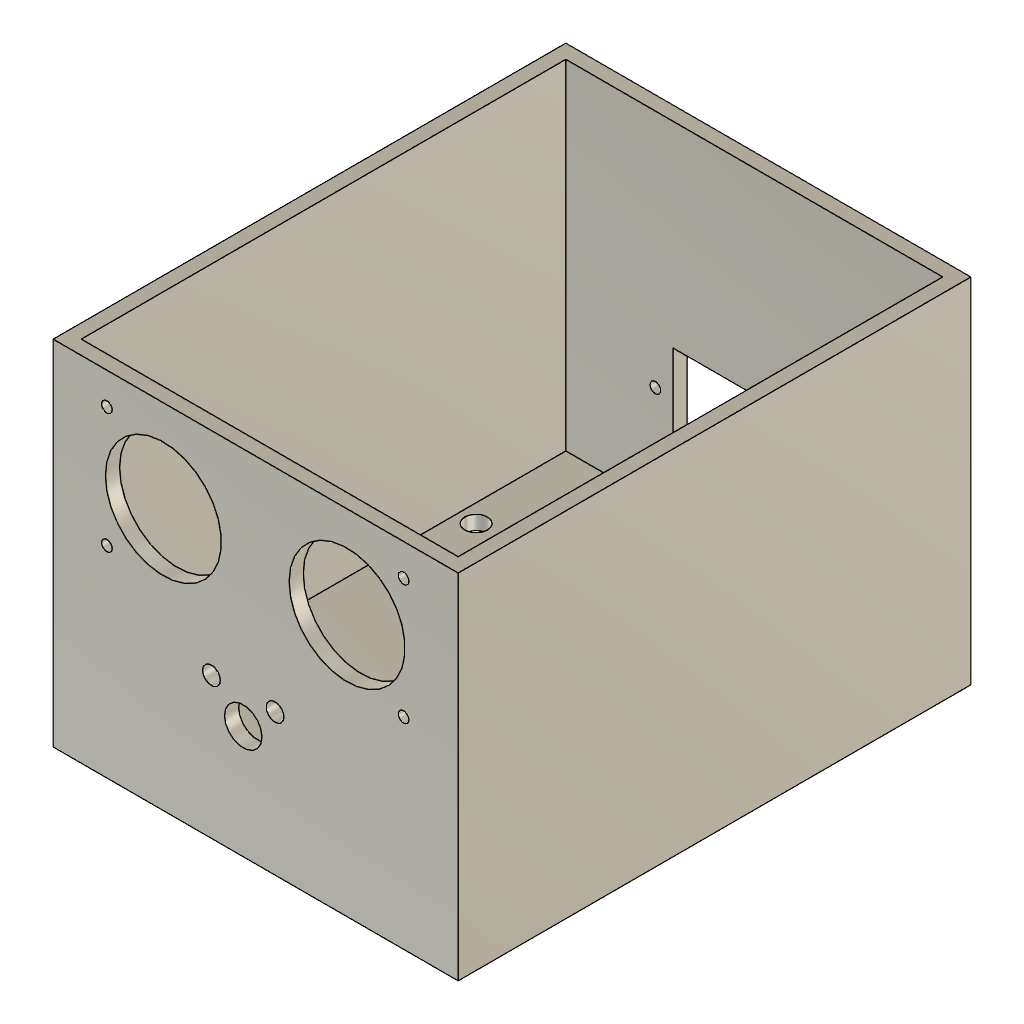
StatusDial_caseV1 (Autodesk Fusion 360 design; units mm, degrees)
part number: 2026-11-27-08-45-43-550
Autodesk Fusion 360 part; units mm, degrees
sketch "Sketch1" plane through (0, 0, 0) normal (0, 0, 1) x (1, 0, 0)
  line L0 (0, 0) -> (53.34, 0)
  line L1 (53.34, 0) -> (53.34, -68.58)
  line L2 (53.34, -68.58) -> (0, -68.58)
  line L3 (0, -68.58) -> (0, 0)
  circle A0 centre (2.54, -15.24) radius 1.6
  circle A1 centre (50.8, -13.97) radius 1.6
  circle A2 centre (17.78, -66.04) radius 1.6
  circle A3 centre (45.72, -66.04) radius 1.6
  line L4 (0, -68.58) -> (-2, -68.58)
  line L5 (0, 0) -> (-2, 0)
  line L6 (-2, -68.58) -> (-2, 0)
  line L7 (-2, 0) -> (-2, 2)
  line L8 (53.34, 0) -> (55.34, 0)
  line L9 (53.34, -68.58) -> (55.34, -68.58)
  line L10 (55.34, -68.58) -> (55.34, 0)
  line L11 (55.34, 0) -> (55.34, -2)
  line L12 (55.34, 0) -> (55.34, 2)
  line L13 (55.34, 2) -> (-2, 2)
  line L14 (-2, -68.58) -> (-2, -70.58)
  line L15 (55.34, -68.58) -> (55.34, -70.58)
  line L16 (55.34, -70.58) -> (-2, -70.58)
  dimension "d1" = 53.34
  dimension "d2" = 68.58
  dimension "d3" = 3.2
  dimension "d4" = 3.2
  dimension "d5" = 3.2
  dimension "d6" = 3.2
  dimension "d7" = 2.54
  dimension "d8" = 15.24
  dimension "d9" = 2.54
  dimension "d10" = 13.97
  dimension "d11" = 17.78
  dimension "d12" = 2.54
  dimension "d13" = 7.62
  dimension "d14" = 2.54
  dimension "d16" = 2
  dimension "d17" = 2
  dimension "d18" = 2
  dimension "d19" = 2
  dimension "d20" = 2
  dimension "d21" = 2
  dimension "d22" = 2
  dimension "d23" = 2
  dimension "d24" = 90
  dimension "d25" = 2
  constraint horizontal L0
  constraint vertical L1
  constraint horizontal L2
  constraint vertical L3
  constraint coincident L0.start L3.end
  constraint perpendicular L3 L4
  constraint perpendicular L3 L5
  constraint perpendicular L5 L7
  constraint perpendicular L1 L8
  constraint perpendicular L1 L9
  constraint perpendicular L8 L11
  constraint perpendicular L8 L12
  constraint perpendicular L9 L15
  measures "d1" distance of L0.start L0.end
  measures "d2" distance of L0.start L2.end
  measures "d3" diameter of A0
  measures "d4" diameter of A1
  measures "d5" diameter of A2
  measures "d6" diameter of A3
  measures "d7" distance of L3 A0.centre
  measures "d8" distance of L0 A0.centre
  measures "d9" distance of L1 A1.centre
  measures "d10" distance of L0 A1.centre
  measures "d11" distance of L3 A2.centre
  measures "d12" distance of L2 A2.centre
  measures "d13" distance of L1 A3.centre
  measures "d14" distance of L2 A3.centre
  measures "d16" distance of L2.end L4.end
  measures "d17" distance of L0.start L5.end
  measures "d18" distance of L5.end L7.end
  measures "d19" distance of L0.end L8.end
  measures "d20" distance of L1.end L9.end
  measures "d21" distance of L8.end L11.end
  measures "d22" distance of L8.end L12.end
  measures "d23" distance of L4.end L14.end
  measures "d24" angle of L13 L14
  measures "d25" distance of L9.end L15.end
extrude "Extrude1" add sketch "Sketch1" along normal blind 50 contours L0 L5 L7 L8 L12 L13 | L3 L4 L5 L6 | L1 L8 L9 L10 L11 | L2 L4 L9 L14 L15 L16
extrude "Extrude2" add sketch "Sketch1" along normal blind 2 contours L0 L1 L2 L3
sketch "Sketch2" plane through (0, -70.58, 0) normal (0, -1, 0) x (1, 0, 0)
  line L0 (-2, 0) -> (55.34, 0)
  line L1 (55.34, 0) -> (55.34, 50)
  line L2 (55.34, 50) -> (-2, 50)
  line L3 (-2, 50) -> (-2, 0)
  line L4 (4.12, 47) -> (49.12, 47)
  line L5 (49.12, 47) -> (49.12, 27)
  line L6 (49.12, 27) -> (4.12, 27)
  line L7 (4.12, 27) -> (4.12, 47)
  circle A0 centre (5.62, 45.5) radius 0.75
  circle A1 centre (47.62, 45.5) radius 0.75
  circle A2 centre (47.62, 28.5) radius 0.75
  circle A3 centre (5.62, 28.5) radius 0.75
  circle A4 centre (13.62, 37) radius 8.2
  circle A5 centre (39.62, 37) radius 8.2
  dimension "d30" = 45
  dimension "d31" = 20
  dimension "d32" = 6.12
  dimension "d33" = 3
  dimension "d34" = 1.5
  dimension "d35" = 1.5
  dimension "d36" = 1.5
  dimension "d37" = 1.5
  dimension "d38" = 1.5
  dimension "d39" = 1.5
  dimension "d40" = 1.5
  dimension "d41" = 1.5
  dimension "d42" = 1.5
  dimension "d43" = 1.5
  dimension "d44" = 1.5
  dimension "d45" = 1.5
  dimension "d46" = 16.4
  dimension "d47" = 16.4
  dimension "d48" = 10
  dimension "d49" = 10
  dimension "d50" = 9.5
  dimension "d51" = 9.5
  constraint horizontal L4
  constraint vertical L5
  constraint horizontal L6
  constraint vertical L7
  measures "d30" distance of L4.start L4.end
  measures "d31" distance of L4.start L6.end
  measures "d32" distance of L3 L7
  measures "d33" distance of L2 L4
  measures "d34" diameter of A0
  measures "d35" diameter of A1
  measures "d36" diameter of A2
  measures "d37" diameter of A3
  measures "d38" distance of L4 A0.centre
  measures "d39" distance of L7 A0.centre
  measures "d40" distance of L4 A1.centre
  measures "d41" distance of L5 A1.centre
  measures "d42" distance of L6 A2.centre
  measures "d43" distance of L5 A2.centre
  measures "d44" distance of L6 A3.centre
  measures "d45" distance of L7 A3.centre
  measures "d46" diameter of A4
  measures "d47" diameter of A5
  measures "d48" distance of L4 A4.centre
  measures "d49" distance of L4 A5.centre
  measures "d50" distance of L5 A5.centre
  measures "d51" distance of L7 A4.centre
extrude "Extrude3" cut sketch "Sketch2" against normal blind 5 contours A0 | A1 | A2 | A3 | A4 | A5
sketch "Sketch3" plane through (0, -70.58, 0) normal (0, -1, 0) x (1, 0, 0)
  line L0 (-2, 0) -> (55.34, 0)
  line L1 (55.34, 0) -> (55.34, 50)
  line L2 (55.34, 50) -> (-2, 50)
  line L3 (-2, 50) -> (-2, 0)
  circle A0 centre (5.62, 45.5) radius 0.75
  circle A1 centre (39.62, 37) radius 8.2
  circle A2 centre (47.62, 28.5) radius 0.75
  circle A3 centre (13.62, 37) radius 8.2
  circle A4 centre (47.62, 45.5) radius 0.75
  circle A5 centre (5.62, 28.5) radius 0.75
  line L4 (17.42, 22.5) -> (32.42, 22.5)
  line L5 (32.42, 22.5) -> (32.42, 4)
  line L6 (32.42, 4) -> (17.42, 4)
  line L7 (17.42, 4) -> (17.42, 22.5)
  circle A6 centre (20.42, 20) radius 1.25
  circle A7 centre (29.42, 20) radius 1.25
  circle A8 centre (24.92, 16) radius 2.65
  dimension "d54" = 15
  dimension "d55" = 18.5
  dimension "d56" = 19.42
  dimension "d57" = 2.5
  dimension "d58" = 2.5
  dimension "d59" = 3
  dimension "d60" = 3
  dimension "d61" = 2.5
  dimension "d62" = 2.5
  dimension "d63" = 5.3
  dimension "d64" = 7.5
  dimension "d65" = 6.5
  dimension "d68" = 4
  constraint horizontal L4
  constraint vertical L5
  constraint horizontal L6
  constraint vertical L7
  measures "d54" distance of L4.start L4.end
  measures "d55" distance of L4.start L6.end
  measures "d56" distance of L3 L7
  measures "d57" diameter of A6
  measures "d58" diameter of A7
  measures "d59" distance of L7 A6.centre
  measures "d60" distance of L5 A7.centre
  measures "d61" distance of L4 A6.centre
  measures "d62" distance of L4 A7.centre
  measures "d63" diameter of A8
  measures "d64" distance of L7 A8.centre
  measures "d65" distance of L4 A8.centre
  measures "d68" distance of L0 L6
extrude "Extrude4" cut sketch "Sketch3" against normal blind 5 contours A6 | A7 | A8
sketch "Sketch4" plane through (0, 2, 0) normal (0, 1, 0) x (-1, 0, 0)
  line L0 (-55.34, 0) -> (2, 0)
  line L1 (2, 0) -> (2, 50)
  line L2 (2, 50) -> (-55.34, 50)
  line L3 (-55.34, 50) -> (-55.34, 0)
  line L4 (-38.17, 22.2) -> (-15.17, 22.2)
  line L5 (-15.17, 22.2) -> (-15.17, 10)
  line L6 (-15.17, 10) -> (-38.17, 10)
  line L7 (-38.17, 10) -> (-38.17, 22.2)
  circle A0 centre (-40.67, 16.1) radius 0.75
  circle A1 centre (-12.67, 16.1) radius 0.75
  dimension "d69" = 23
  dimension "d70" = 12.2
  dimension "d73" = 17.17
  dimension "d74" = 10
  dimension "d75" = 1.5
  dimension "d76" = 1.5
  dimension "d77" = 2.5
  dimension "d78" = 2.5
  dimension "d79" = 6.1
  dimension "d80" = 6.1
  constraint horizontal L4
  constraint vertical L5
  constraint horizontal L6
  constraint vertical L7
  measures "d69" distance of L4.start L4.end
  measures "d70" distance of L4.start L6.end
  measures "d73" distance of L1 L5
  measures "d74" distance of L0 L6
  measures "d75" diameter of A0
  measures "d76" diameter of A1
  measures "d77" distance of L7 A0.centre
  measures "d78" distance of L5 A1.centre
  measures "d79" distance of L4 A1.centre
  measures "d80" distance of L4 A0.centre
extrude "Extrude5" cut sketch "Sketch4" against normal blind 5 contours L4 L5 L6 L7 | A0 | A1
